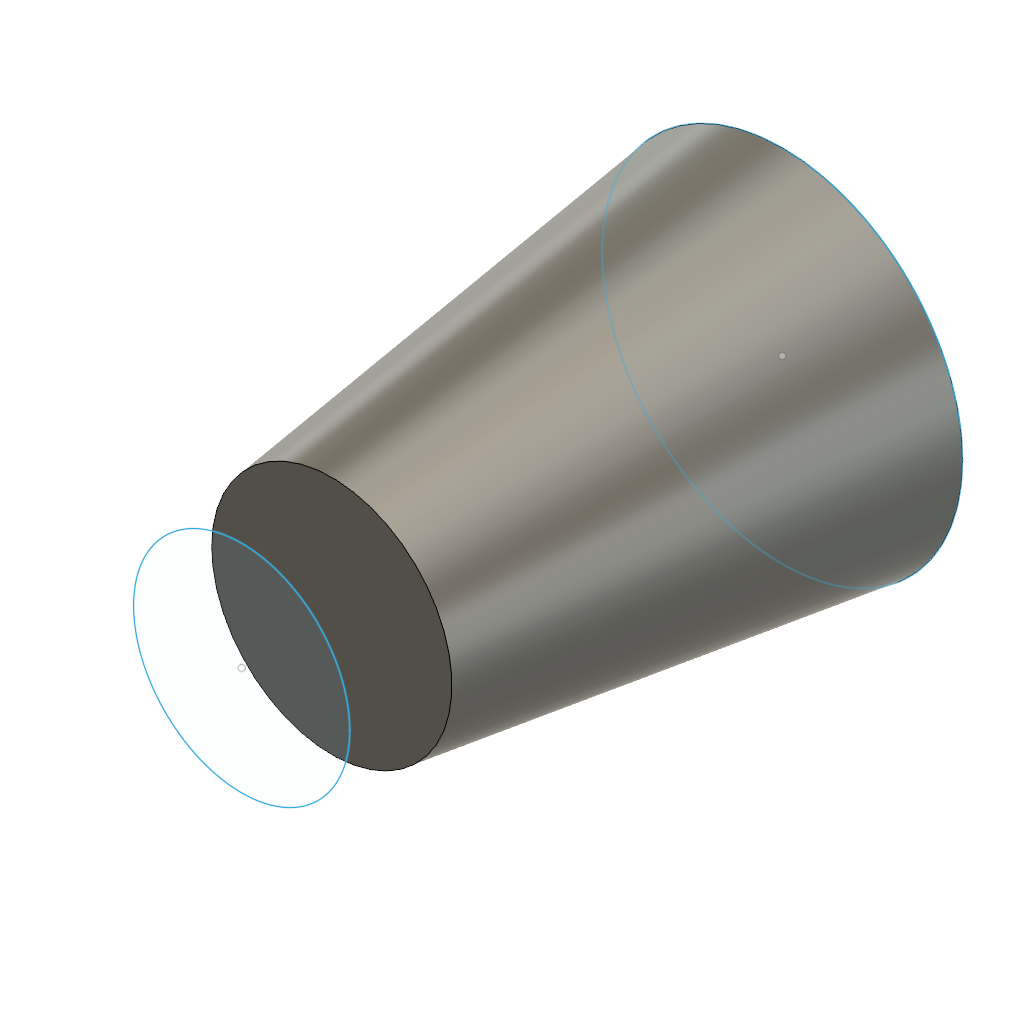
intersect (Autodesk Fusion 360 design; units mm, degrees)
part number: 2026-10-20-22-08-40-725
Autodesk Fusion 360 part; units mm, degrees
ref_plane "WorkPlane1" through (0, 0, -5) normal (0, 0, 1) x (1, 0, 0)
sketch "BlockSection" plane through (0, 0, -5) normal (0, 0, 1) x (1, 0, 0)
  line L0 (-20, -20) -> (20, -20)
  line L1 (20, -20) -> (20, 20)
  line L2 (20, 20) -> (-20, 20)
  line L3 (-20, 20) -> (-20, -20)
extrude "StudyBlockExtrude" add sketch "BlockSection" along normal blind 30
sketch "LoftSection1" plane through (0, 0, 0) normal (0, 0, 1) x (1, 0, 0)
  circle A0 centre (0, 0) radius 10
ref_plane "WorkPlane2" through (0, 0, 30) normal (0, 0, 1) x (1, 0, 0)
sketch "LoftSection2" plane through (0, 0, 30) normal (0, 0, 1) x (1, 0, 0)
  circle A0 centre (0, 0) radius 6
loft "ProbeLoftOperation" cut profiles "LoftSection1", "LoftSection2" section 1 section 2 keep common part
named bodies: "StudyBlock"
